Autodesk Fusion 360 part; units mm, degrees
(part 2 of 2)
ref_plane "WorkPlane31" through (0, 0, 67) normal (0, 0, 1) x (1, 0, 0) in component "02 LID - LCD buttons LEDs"
sketch "V2 text STATUS INDICATORS" plane through (0, 0, 67) normal (0, 0, 1) x (1, 0, 0) in component "02 LID - LCD buttons LEDs"
  line L0 (30, 13) -> (110, 13) construction
  line L1 (110, 13) -> (110, 19) construction
  line L2 (110, 19) -> (30, 19) construction
  line L3 (30, 19) -> (30, 13) construction
  dimension "d425" = 2.5
  text T0 "STATUS INDICATORS" font "Arial" height 2.5 align centre middle in box 80 x 6 at (30, 13) x (1, 0) y (0, 1) spacing 1 kerned
extrude "V2 engrave STATUS INDICATORS" cut sketch "V2 text STATUS INDICATORS" against normal blind 0.35 text T0 bodies 2 in component "02 LID - LCD buttons LEDs"
ref_plane "WorkPlane1" through (0, 0, 67) normal (0, 0, 1) x (1, 0, 0) in component "V2 removable control fascia"
sketch "Control fascia plate sketch" plane through (0, 0, 67) normal (0, 0, 1) x (1, 0, 0) in component "V2 removable control fascia"
  line L0 (42, 22) -> (98, 22)
  line L1 (102, 26) -> (102, 68)
  line L2 (98, 72) -> (42, 72)
  line L3 (38, 68) -> (38, 26)
  arc A0 (98, 22) -> (102, 26) centre (98, 26) ccw
  arc A1 (102, 68) -> (98, 72) centre (98, 68) ccw
  arc A2 (42, 72) -> (38, 68) centre (42, 68) ccw
  arc A3 (38, 26) -> (42, 22) centre (42, 26) ccw
extrude "Control fascia plate" add sketch "Control fascia plate sketch" along normal blind 2.5 separate body makes body 11 in component "V2 removable control fascia"
ref_plane "WorkPlane2" through (0, 0, 66.9) normal (0, 0, 1) x (1, 0, 0) in component "V2 removable control fascia"
sketch "Fascia M3 clearance sketch" plane through (0, 0, 66.9) normal (0, 0, 1) x (1, 0, 0) in component "V2 removable control fascia"
  circle A0 centre (43, 32) radius 1.7
  circle A1 centre (97, 32) radius 1.7
  circle A2 centre (43, 62) radius 1.7
  circle A3 centre (97, 62) radius 1.7
extrude "Fascia M3 clearance" cut sketch "Fascia M3 clearance sketch" along normal blind 2.8 bodies 11 in component "V2 removable control fascia"
ref_plane "WorkPlane3" through (0, 0, 66.9) normal (0, 0, 1) x (1, 0, 0) in component "V2 removable control fascia"
sketch "Tactile actuator guide holes sketch" plane through (0, 0, 66.9) normal (0, 0, 1) x (1, 0, 0) in component "V2 removable control fascia"
  circle A0 centre (62.38, 53) radius 3.05
  circle A1 centre (70, 53) radius 3.05
  circle A2 centre (77.62, 53) radius 3.05
extrude "Tactile actuator guide holes" cut sketch "Tactile actuator guide holes sketch" along normal blind 2.8 bodies 11 in component "V2 removable control fascia"
ref_plane "WorkPlane4" through (0, 0, 66.9) normal (0, 0, 1) x (1, 0, 0) in component "V2 removable control fascia"
sketch "LED common viewing window sketch" plane through (0, 0, 66.9) normal (0, 0, 1) x (1, 0, 0) in component "V2 removable control fascia"
  line L0 (61, 35) -> (79, 35)
  line L1 (81, 37) -> (81, 41)
  line L2 (79, 43) -> (61, 43)
  line L3 (59, 41) -> (59, 37)
  arc A0 (79, 35) -> (81, 37) centre (79, 37) ccw
  arc A1 (81, 41) -> (79, 43) centre (79, 41) ccw
  arc A2 (61, 43) -> (59, 41) centre (61, 41) ccw
  arc A3 (59, 37) -> (61, 35) centre (61, 37) ccw
extrude "LED common viewing window" cut sketch "LED common viewing window sketch" along normal blind 2.8 bodies 11 in component "V2 removable control fascia"
ref_plane "WorkPlane5" through (0, 0, 69.5) normal (0, 0, 1) x (1, 0, 0) in component "V2 removable control fascia"
sketch "V2 text 1" plane through (0, 0, 69.5) normal (0, 0, 1) x (1, 0, 0) in component "V2 removable control fascia"
  line L0 (58.88, 59) -> (65.88, 59) construction
  line L1 (65.88, 59) -> (65.88, 65) construction
  line L2 (65.88, 65) -> (58.88, 65) construction
  line L3 (58.88, 65) -> (58.88, 59) construction
  dimension "d447" = 2.5
  dimension "d448" = 0
  text T0 "1" font "Arial" height 2.5 align centre middle in box 7 x 6 at (58.88, 59) x (1, 0) y (0, 1) spacing 1 kerned
extrude "V2 engrave 1" cut sketch "V2 text 1" against normal blind 0.35 text T0 bodies 11 in component "V2 removable control fascia"
ref_plane "WorkPlane6" through (0, 0, 69.5) normal (0, 0, 1) x (1, 0, 0) in component "V2 removable control fascia"
sketch "V2 text 2" plane through (0, 0, 69.5) normal (0, 0, 1) x (1, 0, 0) in component "V2 removable control fascia"
  line L0 (66.5, 59) -> (73.5, 59) construction
  line L1 (73.5, 59) -> (73.5, 65) construction
  line L2 (73.5, 65) -> (66.5, 65) construction
  line L3 (66.5, 65) -> (66.5, 59) construction
  dimension "d453" = 2.5
  dimension "d454" = 0
  text T0 "2" font "Arial" height 2.5 align centre middle in box 7 x 6 at (66.5, 59) x (1, 0) y (0, 1) spacing 1 kerned
extrude "V2 engrave 2" cut sketch "V2 text 2" against normal blind 0.35 text T0 bodies 11 in component "V2 removable control fascia"
ref_plane "WorkPlane7" through (0, 0, 69.5) normal (0, 0, 1) x (1, 0, 0) in component "V2 removable control fascia"
sketch "V2 text 3" plane through (0, 0, 69.5) normal (0, 0, 1) x (1, 0, 0) in component "V2 removable control fascia"
  line L0 (74.12, 59) -> (81.12, 59) construction
  line L1 (81.12, 59) -> (81.12, 65) construction
  line L2 (81.12, 65) -> (74.12, 65) construction
  line L3 (74.12, 65) -> (74.12, 59) construction
  dimension "d459" = 2.5
  dimension "d460" = 0
  text T0 "3" font "Arial" height 2.5 align centre middle in box 7 x 6 at (74.12, 59) x (1, 0) y (0, 1) spacing 1 kerned
extrude "V2 engrave 3" cut sketch "V2 text 3" against normal blind 0.35 text T0 bodies 11 in component "V2 removable control fascia"
ref_plane "WorkPlane32" through (0, 0, 63.9) normal (0, 0, 1) x (1, 0, 0) in component "02 LID - LCD buttons LEDs"
sketch "V2 carrier pillar clearance in lid sketch" plane through (0, 0, 63.9) normal (0, 0, 1) x (1, 0, 0) in component "02 LID - LCD buttons LEDs"
  circle A0 centre (45, 44) radius 4.1
  circle A1 centre (95, 44) radius 4.1
extrude "V2 carrier pillar clearance in lid" cut sketch "V2 carrier pillar clearance in lid sketch" along normal blind 3.3 bodies 2 in component "02 LID - LCD buttons LEDs"
ref_plane "WorkPlane8" through (0, 0, 49) normal (0, 0, 1) x (1, 0, 0) in component "V2 removable control fascia"
sketch "Control carrier standoffs sketch" plane through (0, 0, 49) normal (0, 0, 1) x (1, 0, 0) in component "V2 removable control fascia"
  circle A0 centre (45, 44) radius 3.5
  circle A1 centre (95, 44) radius 3.5
extrude "Control carrier standoffs" add sketch "Control carrier standoffs sketch" along normal blind 18 bodies 11 in component "V2 removable control fascia"
ref_plane "WorkPlane9" through (0, 0, 48.9) normal (0, 0, 1) x (1, 0, 0) in component "V2 removable control fascia"
sketch "Carrier M3 pilots sketch" plane through (0, 0, 48.9) normal (0, 0, 1) x (1, 0, 0) in component "V2 removable control fascia"
  circle A0 centre (45, 44) radius 1.25
  circle A1 centre (95, 44) radius 1.25
extrude "Carrier M3 pilots" cut sketch "Carrier M3 pilots sketch" along normal blind 8.1 bodies 11 in component "V2 removable control fascia"
ref_plane "WorkPlane1" through (0, 0, 46.5) normal (0, 0, 1) x (1, 0, 0) in component "V2 control PCB removable carrier"
sketch "Control PCB carrier sketch" plane through (0, 0, 46.5) normal (0, 0, 1) x (1, 0, 0) in component "V2 control PCB removable carrier"
  line L0 (42, 28) -> (98, 28)
  line L1 (100, 30) -> (100, 61)
  line L2 (98, 63) -> (42, 63)
  line L3 (40, 61) -> (40, 30)
  arc A0 (98, 28) -> (100, 30) centre (98, 30) ccw
  arc A1 (100, 61) -> (98, 63) centre (98, 61) ccw
  arc A2 (42, 63) -> (40, 61) centre (42, 61) ccw
  arc A3 (40, 30) -> (42, 28) centre (42, 30) ccw
extrude "Control PCB carrier" add sketch "Control PCB carrier sketch" along normal blind 2.5 separate body makes body 12 in component "V2 control PCB removable carrier"
ref_plane "WorkPlane2" through (0, 0, 46.4) normal (0, 0, 1) x (1, 0, 0) in component "V2 control PCB removable carrier"
sketch "Carrier M3 through sketch" plane through (0, 0, 46.4) normal (0, 0, 1) x (1, 0, 0) in component "V2 control PCB removable carrier"
  circle A0 centre (45, 44) radius 1.7
  circle A1 centre (95, 44) radius 1.7
extrude "Carrier M3 through" cut sketch "Carrier M3 through sketch" along normal blind 2.8 bodies 12 in component "V2 control PCB removable carrier"
ref_plane "WorkPlane3" through (0, 0, 49) normal (0, 0, 1) x (1, 0, 0) in component "V2 control PCB removable carrier"
sketch "Control PCB corner support pads" plane through (0, 0, 49) normal (0, 0, 1) x (1, 0, 0) in component "V2 control PCB removable carrier"
  line L0 (54, 30) -> (57, 30)
  line L1 (57, 30) -> (57, 33)
  line L2 (57, 33) -> (54, 33)
  line L3 (54, 33) -> (54, 30)
  line L4 (54, 57) -> (57, 57)
  line L5 (57, 57) -> (57, 60)
  line L6 (57, 60) -> (54, 60)
  line L7 (54, 60) -> (54, 57)
  line L8 (83, 30) -> (86, 30)
  line L9 (86, 30) -> (86, 33)
  line L10 (86, 33) -> (83, 33)
  line L11 (83, 33) -> (83, 30)
  line L12 (83, 57) -> (86, 57)
  line L13 (86, 57) -> (86, 60)
  line L14 (86, 60) -> (83, 60)
  line L15 (83, 60) -> (83, 57)
extrude "PCB stand-off pads" add sketch "Control PCB corner support pads" along normal blind 4 bodies 12 in component "V2 control PCB removable carrier"
ref_plane "WorkPlane4" through (0, 0, 49) normal (0, 0, 1) x (1, 0, 0) in component "V2 control PCB removable carrier"
sketch "Control PCB guide sketch" plane through (0, 0, 49) normal (0, 0, 1) x (1, 0, 0) in component "V2 control PCB removable carrier"
  line L0 (51.5, 30) -> (53.5, 30)
  line L1 (53.5, 30) -> (53.5, 60)
  line L2 (53.5, 60) -> (51.5, 60)
  line L3 (51.5, 60) -> (51.5, 30)
extrude "Control PCB guide" add sketch "Control PCB guide sketch" along normal blind 5 bodies 12 in component "V2 control PCB removable carrier"
ref_plane "WorkPlane5" through (0, 0, 49) normal (0, 0, 1) x (1, 0, 0) in component "V2 control PCB removable carrier"
sketch "Control PCB guide sketch (1)" plane through (0, 0, 49) normal (0, 0, 1) x (1, 0, 0) in component "V2 control PCB removable carrier"
  line L0 (86.5, 30) -> (88.5, 30)
  line L1 (88.5, 30) -> (88.5, 60)
  line L2 (88.5, 60) -> (86.5, 60)
  line L3 (86.5, 60) -> (86.5, 30)
extrude "Control PCB guide (1)" add sketch "Control PCB guide sketch (1)" along normal blind 5 bodies 12 in component "V2 control PCB removable carrier"
ref_plane "WorkPlane6" through (0, 0, 49) normal (0, 0, 1) x (1, 0, 0) in component "V2 control PCB removable carrier"
sketch "Control PCB guide sketch (2)" plane through (0, 0, 49) normal (0, 0, 1) x (1, 0, 0) in component "V2 control PCB removable carrier"
  line L0 (54, 27.5) -> (86, 27.5)
  line L1 (86, 27.5) -> (86, 29.5)
  line L2 (86, 29.5) -> (54, 29.5)
  line L3 (54, 29.5) -> (54, 27.5)
extrude "Control PCB guide (2)" add sketch "Control PCB guide sketch (2)" along normal blind 5 bodies 12 in component "V2 control PCB removable carrier"
ref_plane "WorkPlane7" through (0, 0, 46.4) normal (0, 0, 1) x (1, 0, 0) in component "V2 control PCB removable carrier"
sketch "PCB retaining strap slot sketch" plane through (0, 0, 46.4) normal (0, 0, 1) x (1, 0, 0) in component "V2 control PCB removable carrier"
  line L0 (52, 48) -> (54, 48)
  line L1 (54, 48) -> (54, 54)
  line L2 (54, 54) -> (52, 54)
  line L3 (52, 54) -> (52, 48)
extrude "PCB retaining strap slot" cut sketch "PCB retaining strap slot sketch" along normal blind 2.8 bodies 12 in component "V2 control PCB removable carrier"
ref_plane "WorkPlane8" through (0, 0, 46.4) normal (0, 0, 1) x (1, 0, 0) in component "V2 control PCB removable carrier"
sketch "PCB retaining strap slot sketch (1)" plane through (0, 0, 46.4) normal (0, 0, 1) x (1, 0, 0) in component "V2 control PCB removable carrier"
  line L0 (85, 48) -> (87, 48)
  line L1 (87, 48) -> (87, 54)
  line L2 (87, 54) -> (85, 54)
  line L3 (85, 54) -> (85, 48)
extrude "PCB retaining strap slot (1)" cut sketch "PCB retaining strap slot sketch (1)" along normal blind 2.8 bodies 12 in component "V2 control PCB removable carrier"
ref_plane "WorkPlane1" through (0, 0, 58.6) normal (0, 0, 1) x (1, 0, 0) in component "V2 captured tactile plunger 1"
sketch "Tactile contact stem" plane through (0, 0, 58.6) normal (0, 0, 1) x (1, 0, 0) in component "V2 captured tactile plunger 1"
  circle A0 centre (62.38, 53) radius 2
extrude "Tactile contact stem (1)" add sketch "Tactile contact stem" along normal blind 8.2 separate body makes body 13 in component "V2 captured tactile plunger 1"
ref_plane "WorkPlane2" through (0, 0, 65.2) normal (0, 0, 1) x (1, 0, 0) in component "V2 captured tactile plunger 1"
sketch "Captive flange" plane through (0, 0, 65.2) normal (0, 0, 1) x (1, 0, 0) in component "V2 captured tactile plunger 1"
  circle A0 centre (62.38, 53) radius 3.5
extrude "Captive flange (1)" add sketch "Captive flange" along normal blind 1.6 bodies 13 in component "V2 captured tactile plunger 1"
ref_plane "WorkPlane3" through (0, 0, 66.8) normal (0, 0, 1) x (1, 0, 0) in component "V2 captured tactile plunger 1"
sketch "Finger tip" plane through (0, 0, 66.8) normal (0, 0, 1) x (1, 0, 0) in component "V2 captured tactile plunger 1"
  circle A0 centre (62.38, 53) radius 2.75
extrude "Finger tip (1)" add sketch "Finger tip" along normal blind 3.6 bodies 13 in component "V2 captured tactile plunger 1"
ref_plane "WorkPlane1" through (0, 0, 58.6) normal (0, 0, 1) x (1, 0, 0) in component "V2 captured tactile plunger 2"
sketch "Tactile contact stem (2)" plane through (0, 0, 58.6) normal (0, 0, 1) x (1, 0, 0) in component "V2 captured tactile plunger 2"
  circle A0 centre (70, 53) radius 2
extrude "Tactile contact stem (1)'" add sketch "Tactile contact stem (2)" along normal blind 8.2 separate body makes body 14 in component "V2 captured tactile plunger 2"
ref_plane "WorkPlane2" through (0, 0, 65.2) normal (0, 0, 1) x (1, 0, 0) in component "V2 captured tactile plunger 2"
sketch "Captive flange (2)" plane through (0, 0, 65.2) normal (0, 0, 1) x (1, 0, 0) in component "V2 captured tactile plunger 2"
  circle A0 centre (70, 53) radius 3.5
extrude "Captive flange (1)'" add sketch "Captive flange (2)" along normal blind 1.6 bodies 14 in component "V2 captured tactile plunger 2"
ref_plane "WorkPlane3" through (0, 0, 66.8) normal (0, 0, 1) x (1, 0, 0) in component "V2 captured tactile plunger 2"
sketch "Finger tip (2)" plane through (0, 0, 66.8) normal (0, 0, 1) x (1, 0, 0) in component "V2 captured tactile plunger 2"
  circle A0 centre (70, 53) radius 2.75
extrude "Finger tip (1)'" add sketch "Finger tip (2)" along normal blind 3.6 bodies 14 in component "V2 captured tactile plunger 2"
ref_plane "WorkPlane1" through (0, 0, 58.6) normal (0, 0, 1) x (1, 0, 0) in component "V2 captured tactile plunger 3"
sketch "Tactile contact stem (3)" plane through (0, 0, 58.6) normal (0, 0, 1) x (1, 0, 0) in component "V2 captured tactile plunger 3"
  circle A0 centre (77.62, 53) radius 2
extrude "Tactile contact stem (1)''" add sketch "Tactile contact stem (3)" along normal blind 8.2 separate body makes body 15 in component "V2 captured tactile plunger 3"
ref_plane "WorkPlane2" through (0, 0, 65.2) normal (0, 0, 1) x (1, 0, 0) in component "V2 captured tactile plunger 3"
sketch "Captive flange (3)" plane through (0, 0, 65.2) normal (0, 0, 1) x (1, 0, 0) in component "V2 captured tactile plunger 3"
  circle A0 centre (77.62, 53) radius 3.5
extrude "Captive flange (1)''" add sketch "Captive flange (3)" along normal blind 1.6 bodies 15 in component "V2 captured tactile plunger 3"
ref_plane "WorkPlane3" through (0, 0, 66.8) normal (0, 0, 1) x (1, 0, 0) in component "V2 captured tactile plunger 3"
sketch "Finger tip (3)" plane through (0, 0, 66.8) normal (0, 0, 1) x (1, 0, 0) in component "V2 captured tactile plunger 3"
  circle A0 centre (77.62, 53) radius 2.75
extrude "Finger tip (1)''" add sketch "Finger tip (3)" along normal blind 3.6 bodies 15 in component "V2 captured tactile plunger 3"
ref_plane "WorkPlane1" through (0, 0, 8) normal (0, 0, 1) x (1, 0, 0) in component "REF main board 90x80x20 - photo estimate"
sketch "Main PCB sketch" plane through (0, 0, 8) normal (0, 0, 1) x (1, 0, 0) in component "REF main board 90x80x20 - photo estimate"
  line L0 (25, 20) -> (115, 20)
  line L1 (115, 20) -> (115, 100)
  line L2 (115, 100) -> (25, 100)
  line L3 (25, 100) -> (25, 20)
extrude "Main PCB" add sketch "Main PCB sketch" along normal blind 1.6 separate body makes body 16 in component "REF main board 90x80x20 - photo estimate"
ref_plane "WorkPlane2" through (0, 0, 9.6) normal (0, 0, 1) x (1, 0, 0) in component "REF main board 90x80x20 - photo estimate"
sketch "ESP32 reference sketch" plane through (0, 0, 9.6) normal (0, 0, 1) x (1, 0, 0) in component "REF main board 90x80x20 - photo estimate"
  line L0 (68, 38) -> (95, 38)
  line L1 (95, 38) -> (95, 88)
  line L2 (95, 88) -> (68, 88)
  line L3 (68, 88) -> (68, 38)
extrude "ESP32 reference" add sketch "ESP32 reference sketch" along normal blind 12 separate body makes body 17 in component "REF main board 90x80x20 - photo estimate"
ref_plane "WorkPlane3" through (0, 0, 9.6) normal (0, 0, 1) x (1, 0, 0) in component "REF main board 90x80x20 - photo estimate"
sketch "nRF24 reference sketch" plane through (0, 0, 9.6) normal (0, 0, 1) x (1, 0, 0) in component "REF main board 90x80x20 - photo estimate"
  line L0 (33, 75) -> (68, 75)
  line L1 (68, 75) -> (68, 93)
  line L2 (68, 93) -> (33, 93)
  line L3 (33, 93) -> (33, 75)
extrude "nRF24 reference" add sketch "nRF24 reference sketch" along normal blind 10 separate body makes body 18 in component "REF main board 90x80x20 - photo estimate"
ref_plane "WorkPlane4" through (0, 0, 9.6) normal (0, 0, 1) x (1, 0, 0) in component "REF main board 90x80x20 - photo estimate"
sketch "MPU6050 reference sketch" plane through (0, 0, 9.6) normal (0, 0, 1) x (1, 0, 0) in component "REF main board 90x80x20 - photo estimate"
  line L0 (36, 34) -> (57, 34)
  line L1 (57, 34) -> (57, 50)
  line L2 (57, 50) -> (36, 50)
  line L3 (36, 50) -> (36, 34)
extrude "MPU6050 reference" add sketch "MPU6050 reference sketch" along normal blind 6 separate body makes body 19 in component "REF main board 90x80x20 - photo estimate"
ref_plane "WorkPlane5" through (0, 0, 9.6) normal (0, 0, 1) x (1, 0, 0) in component "REF main board 90x80x20 - photo estimate"
sketch "Tallest component 20mm total sketch" plane through (0, 0, 9.6) normal (0, 0, 1) x (1, 0, 0) in component "REF main board 90x80x20 - photo estimate"
  line L0 (62, 22) -> (72, 22)
  line L1 (72, 22) -> (72, 32)
  line L2 (72, 32) -> (62, 32)
  line L3 (62, 32) -> (62, 22)
extrude "Tallest component 20mm total" add sketch "Tallest component 20mm total sketch" along normal blind 18.4 separate body makes body 20 in component "REF main board 90x80x20 - photo estimate"
ref_plane "WorkPlane6" through (0, 0, 11) normal (0, 0, 1) x (1, 0, 0) in component "REF main board 90x80x20 - photo estimate"
sketch "Rocker switch side clearance sketch" plane through (0, 0, 11) normal (0, 0, 1) x (1, 0, 0) in component "REF main board 90x80x20 - photo estimate"
  line L0 (18, 23) -> (25, 23)
  line L1 (25, 23) -> (25, 39)
  line L2 (25, 39) -> (18, 39)
  line L3 (18, 39) -> (18, 23)
extrude "Rocker switch side clearance" add sketch "Rocker switch side clearance sketch" along normal blind 12 separate body makes body 21 in component "REF main board 90x80x20 - photo estimate"
ref_plane "WorkPlane7" through (0, 0, 13) normal (0, 0, 1) x (1, 0, 0) in component "REF main board 90x80x20 - photo estimate"
sketch "SMA connector space sketch" plane through (0, 0, 13) normal (0, 0, 1) x (1, 0, 0) in component "REF main board 90x80x20 - photo estimate"
  line L0 (16, 80) -> (25, 80)
  line L1 (25, 80) -> (25, 86)
  line L2 (25, 86) -> (16, 86)
  line L3 (16, 86) -> (16, 80)
extrude "SMA connector space" add sketch "SMA connector space sketch" along normal blind 6 separate body makes body 22 in component "REF main board 90x80x20 - photo estimate"
ref_plane "WorkPlane1" through (0, 0, 8) normal (0, 0, 1) x (1, 0, 0) in component "REF four relay board 70x50x20"
sketch "Relay PCB sketch" plane through (0, 0, 8) normal (0, 0, 1) x (1, 0, 0) in component "REF four relay board 70x50x20"
  line L0 (35, 117) -> (105, 117)
  line L1 (105, 117) -> (105, 167)
  line L2 (105, 167) -> (35, 167)
  line L3 (35, 167) -> (35, 117)
extrude "Relay PCB" add sketch "Relay PCB sketch" along normal blind 1.6 separate body makes body 23 in component "REF four relay board 70x50x20"
ref_plane "WorkPlane2" through (0, 0, 9.6) normal (0, 0, 1) x (1, 0, 0) in component "REF four relay board 70x50x20"
sketch "Relay 1 sketch" plane through (0, 0, 9.6) normal (0, 0, 1) x (1, 0, 0) in component "REF four relay board 70x50x20"
  line L0 (38, 133) -> (53, 133)
  line L1 (53, 133) -> (53, 152)
  line L2 (53, 152) -> (38, 152)
  line L3 (38, 152) -> (38, 133)
extrude "Relay 1" add sketch "Relay 1 sketch" along normal blind 15.5 separate body makes body 24 in component "REF four relay board 70x50x20"
ref_plane "WorkPlane3" through (0, 0, 9.6) normal (0, 0, 1) x (1, 0, 0) in component "REF four relay board 70x50x20"
sketch "Relay 2 sketch" plane through (0, 0, 9.6) normal (0, 0, 1) x (1, 0, 0) in component "REF four relay board 70x50x20"
  line L0 (54, 133) -> (69, 133)
  line L1 (69, 133) -> (69, 152)
  line L2 (69, 152) -> (54, 152)
  line L3 (54, 152) -> (54, 133)
extrude "Relay 2" add sketch "Relay 2 sketch" along normal blind 15.5 separate body makes body 25 in component "REF four relay board 70x50x20"
ref_plane "WorkPlane4" through (0, 0, 9.6) normal (0, 0, 1) x (1, 0, 0) in component "REF four relay board 70x50x20"
sketch "Relay 3 sketch" plane through (0, 0, 9.6) normal (0, 0, 1) x (1, 0, 0) in component "REF four relay board 70x50x20"
  line L0 (70, 133) -> (85, 133)
  line L1 (85, 133) -> (85, 152)
  line L2 (85, 152) -> (70, 152)
  line L3 (70, 152) -> (70, 133)
extrude "Relay 3" add sketch "Relay 3 sketch" along normal blind 15.5 separate body makes body 26 in component "REF four relay board 70x50x20"
ref_plane "WorkPlane5" through (0, 0, 9.6) normal (0, 0, 1) x (1, 0, 0) in component "REF four relay board 70x50x20"
sketch "Relay 4 sketch" plane through (0, 0, 9.6) normal (0, 0, 1) x (1, 0, 0) in component "REF four relay board 70x50x20"
  line L0 (86, 133) -> (101, 133)
  line L1 (101, 133) -> (101, 152)
  line L2 (101, 152) -> (86, 152)
  line L3 (86, 152) -> (86, 133)
extrude "Relay 4" add sketch "Relay 4 sketch" along normal blind 15.5 separate body makes body 27 in component "REF four relay board 70x50x20"
ref_plane "WorkPlane6" through (0, 0, 9.6) normal (0, 0, 1) x (1, 0, 0) in component "REF four relay board 70x50x20"
sketch "Screw terminal strip sketch" plane through (0, 0, 9.6) normal (0, 0, 1) x (1, 0, 0) in component "REF four relay board 70x50x20"
  line L0 (38, 155) -> (100, 155)
  line L1 (100, 155) -> (100, 165)
  line L2 (100, 165) -> (38, 165)
  line L3 (38, 165) -> (38, 155)
extrude "Screw terminal strip" add sketch "Screw terminal strip sketch" along normal blind 12 separate body makes body 28 in component "REF four relay board 70x50x20"
ref_plane "WorkPlane7" through (0, 0, 9.6) normal (0, 0, 1) x (1, 0, 0) in component "REF four relay board 70x50x20"
sketch "Relay control connector envelope sketch" plane through (0, 0, 9.6) normal (0, 0, 1) x (1, 0, 0) in component "REF four relay board 70x50x20"
  line L0 (42, 119) -> (77, 119)
  line L1 (77, 119) -> (77, 124)
  line L2 (77, 124) -> (42, 124)
  line L3 (42, 124) -> (42, 119)
extrude "Relay control connector envelope" add sketch "Relay control connector envelope sketch" along normal blind 18.4 separate body makes body 29 in component "REF four relay board 70x50x20"
ref_plane "WorkPlane1" through (0, 0, 52.4) normal (0, 0, 1) x (1, 0, 0) in component "REF LCD2004 98x60 - estimated from photo"
sketch "LCD PCB sketch" plane through (0, 0, 52.4) normal (0, 0, 1) x (1, 0, 0) in component "REF LCD2004 98x60 - estimated from photo"
  line L0 (21, 98) -> (119, 98)
  line L1 (119, 98) -> (119, 158)
  line L2 (119, 158) -> (21, 158)
  line L3 (21, 158) -> (21, 98)
extrude "LCD PCB" add sketch "LCD PCB sketch" along normal blind 1.6 separate body makes body 30 in component "REF LCD2004 98x60 - estimated from photo"
ref_plane "WorkPlane2" through (0, 0, 52.3) normal (0, 0, 1) x (1, 0, 0) in component "REF LCD2004 98x60 - estimated from photo"
sketch "LCD reference mounting holes sketch" plane through (0, 0, 52.3) normal (0, 0, 1) x (1, 0, 0) in component "REF LCD2004 98x60 - estimated from photo"
  circle A0 centre (23.5, 100.5) radius 1.6
  circle A1 centre (116.5, 100.5) radius 1.6
  circle A2 centre (23.5, 155.5) radius 1.6
  circle A3 centre (116.5, 155.5) radius 1.6
extrude "LCD reference mounting holes" cut sketch "LCD reference mounting holes sketch" along normal blind 1.8 bodies 30 in component "REF LCD2004 98x60 - estimated from photo"
ref_plane "WorkPlane3" through (0, 0, 54) normal (0, 0, 1) x (1, 0, 0) in component "REF LCD2004 98x60 - estimated from photo"
sketch "LCD bezel sketch" plane through (0, 0, 54) normal (0, 0, 1) x (1, 0, 0) in component "REF LCD2004 98x60 - estimated from photo"
  line L0 (21.5, 108.5) -> (118.5, 108.5)
  line L1 (118.5, 108.5) -> (118.5, 147.5)
  line L2 (118.5, 147.5) -> (21.5, 147.5)
  line L3 (21.5, 147.5) -> (21.5, 108.5)
extrude "LCD bezel" add sketch "LCD bezel sketch" along normal blind 9.5 separate body makes body 31 in component "REF LCD2004 98x60 - estimated from photo"
ref_plane "WorkPlane4" through (0, 0, 63.5) normal (0, 0, 1) x (1, 0, 0) in component "REF LCD2004 98x60 - estimated from photo"
sketch "LCD glass sketch" plane through (0, 0, 63.5) normal (0, 0, 1) x (1, 0, 0) in component "REF LCD2004 98x60 - estimated from photo"
  line L0 (32, 115.4) -> (108, 115.4)
  line L1 (108, 115.4) -> (108, 140.6)
  line L2 (108, 140.6) -> (32, 140.6)
  line L3 (32, 140.6) -> (32, 115.4)
extrude "LCD glass" add sketch "LCD glass sketch" along normal blind 0.3 separate body makes body 32 in component "REF LCD2004 98x60 - estimated from photo"
ref_plane "WorkPlane5" through (0, 0, 42) normal (0, 0, 1) x (1, 0, 0) in component "REF LCD2004 98x60 - estimated from photo"
sketch "LCD backpack reserve sketch" plane through (0, 0, 42) normal (0, 0, 1) x (1, 0, 0) in component "REF LCD2004 98x60 - estimated from photo"
  line L0 (32, 100) -> (74, 100)
  line L1 (74, 100) -> (74, 118)
  line L2 (74, 118) -> (32, 118)
  line L3 (32, 118) -> (32, 100)
extrude "LCD backpack reserve" add sketch "LCD backpack reserve sketch" along normal blind 10.4 separate body makes body 33 in component "REF LCD2004 98x60 - estimated from photo"
ref_plane "WorkPlane1" through (0, 0, 53) normal (0, 0, 1) x (1, 0, 0) in component "REF actual combined buttons LEDs PCB - estimated"
sketch "Control PCB estimated 30x30 sketch" plane through (0, 0, 53) normal (0, 0, 1) x (1, 0, 0) in component "REF actual combined buttons LEDs PCB - estimated"
  line L0 (55, 30) -> (85, 30)
  line L1 (85, 30) -> (85, 60)
  line L2 (85, 60) -> (55, 60)
  line L3 (55, 60) -> (55, 30)
extrude "Control PCB estimated 30x30" add sketch "Control PCB estimated 30x30 sketch" along normal blind 1.6 separate body makes body 34 in component "REF actual combined buttons LEDs PCB - estimated"
ref_plane "WorkPlane2" through (0, 0, 54.6) normal (0, 0, 1) x (1, 0, 0) in component "REF actual combined buttons LEDs PCB - estimated"
sketch "Tactile switch 6x6 sketch" plane through (0, 0, 54.6) normal (0, 0, 1) x (1, 0, 0) in component "REF actual combined buttons LEDs PCB - estimated"
  line L0 (59.38, 50) -> (65.38, 50)
  line L1 (65.38, 50) -> (65.38, 56)
  line L2 (65.38, 56) -> (59.38, 56)
  line L3 (59.38, 56) -> (59.38, 50)
extrude "Tactile switch 6x6" add sketch "Tactile switch 6x6 sketch" along normal blind 3.3 separate body makes body 35 in component "REF actual combined buttons LEDs PCB - estimated"
ref_plane "WorkPlane3" through (0, 0, 57.9) normal (0, 0, 1) x (1, 0, 0) in component "REF actual combined buttons LEDs PCB - estimated"
sketch "Switch actuator" plane through (0, 0, 57.9) normal (0, 0, 1) x (1, 0, 0) in component "REF actual combined buttons LEDs PCB - estimated"
  circle A0 centre (62.38, 53) radius 1.65
extrude "Switch actuator (1)" add sketch "Switch actuator" along normal blind 0.5 separate body makes body 36 in component "REF actual combined buttons LEDs PCB - estimated"
ref_plane "WorkPlane4" through (0, 0, 54.6) normal (0, 0, 1) x (1, 0, 0) in component "REF actual combined buttons LEDs PCB - estimated"
sketch "Tactile switch 6x6 sketch (1)" plane through (0, 0, 54.6) normal (0, 0, 1) x (1, 0, 0) in component "REF actual combined buttons LEDs PCB - estimated"
  line L0 (67, 50) -> (73, 50)
  line L1 (73, 50) -> (73, 56)
  line L2 (73, 56) -> (67, 56)
  line L3 (67, 56) -> (67, 50)
extrude "Tactile switch 6x6 (1)" add sketch "Tactile switch 6x6 sketch (1)" along normal blind 3.3 separate body makes body 37 in component "REF actual combined buttons LEDs PCB - estimated"
ref_plane "WorkPlane5" through (0, 0, 57.9) normal (0, 0, 1) x (1, 0, 0) in component "REF actual combined buttons LEDs PCB - estimated"
sketch "Switch actuator (1)" plane through (0, 0, 57.9) normal (0, 0, 1) x (1, 0, 0) in component "REF actual combined buttons LEDs PCB - estimated"
  circle A0 centre (70, 53) radius 1.65
extrude "Switch actuator (2)" add sketch "Switch actuator (1)" along normal blind 0.5 separate body makes body 38 in component "REF actual combined buttons LEDs PCB - estimated"
ref_plane "WorkPlane6" through (0, 0, 54.6) normal (0, 0, 1) x (1, 0, 0) in component "REF actual combined buttons LEDs PCB - estimated"
sketch "Tactile switch 6x6 sketch (2)" plane through (0, 0, 54.6) normal (0, 0, 1) x (1, 0, 0) in component "REF actual combined buttons LEDs PCB - estimated"
  line L0 (74.62, 50) -> (80.62, 50)
  line L1 (80.62, 50) -> (80.62, 56)
  line L2 (80.62, 56) -> (74.62, 56)
  line L3 (74.62, 56) -> (74.62, 50)
extrude "Tactile switch 6x6 (2)" add sketch "Tactile switch 6x6 sketch (2)" along normal blind 3.3 separate body makes body 39 in component "REF actual combined buttons LEDs PCB - estimated"
ref_plane "WorkPlane7" through (0, 0, 57.9) normal (0, 0, 1) x (1, 0, 0) in component "REF actual combined buttons LEDs PCB - estimated"
sketch "Switch actuator (2)" plane through (0, 0, 57.9) normal (0, 0, 1) x (1, 0, 0) in component "REF actual combined buttons LEDs PCB - estimated"
  circle A0 centre (77.62, 53) radius 1.65
extrude "Switch actuator (3)" add sketch "Switch actuator (2)" along normal blind 0.5 separate body makes body 40 in component "REF actual combined buttons LEDs PCB - estimated"
ref_plane "WorkPlane8" through (0, 0, 54.6) normal (0, 0, 1) x (1, 0, 0) in component "REF actual combined buttons LEDs PCB - estimated"
sketch "LED BLUE" plane through (0, 0, 54.6) normal (0, 0, 1) x (1, 0, 0) in component "REF actual combined buttons LEDs PCB - estimated"
  circle A0 centre (63.65, 39) radius 1.5
extrude "LED BLUE (1)" add sketch "LED BLUE" along normal blind 4.5 separate body makes body 41 in component "REF actual combined buttons LEDs PCB - estimated"
ref_plane "WorkPlane9" through (0, 0, 54.6) normal (0, 0, 1) x (1, 0, 0) in component "REF actual combined buttons LEDs PCB - estimated"
sketch "LED RED" plane through (0, 0, 54.6) normal (0, 0, 1) x (1, 0, 0) in component "REF actual combined buttons LEDs PCB - estimated"
  circle A0 centre (70, 39) radius 1.5
extrude "LED RED (1)" add sketch "LED RED" along normal blind 4.5 separate body makes body 42 in component "REF actual combined buttons LEDs PCB - estimated"
ref_plane "WorkPlane10" through (0, 0, 54.6) normal (0, 0, 1) x (1, 0, 0) in component "REF actual combined buttons LEDs PCB - estimated"
sketch "LED GREEN" plane through (0, 0, 54.6) normal (0, 0, 1) x (1, 0, 0) in component "REF actual combined buttons LEDs PCB - estimated"
  circle A0 centre (76.35, 39) radius 1.5
extrude "LED GREEN (1)" add sketch "LED GREEN" along normal blind 4.5 separate body makes body 43 in component "REF actual combined buttons LEDs PCB - estimated"
ref_plane "WorkPlane23" through (0, 0, 14) normal (0, 0, 1) x (1, 0, 0) in component "01 BASE - PCB at bottom"
sketch "V2 repaired rear cable outlet sketch" plane through (0, 0, 14) normal (0, 0, 1) x (1, 0, 0) in component "01 BASE - PCB at bottom"
  line L0 (38, 176.5) -> (62, 176.5)
  line L1 (62, 176.5) -> (62, 180.5)
  line L2 (62, 180.5) -> (38, 180.5)
  line L3 (38, 180.5) -> (38, 176.5)
extrude "V2 repaired rear cable outlet" cut sketch "V2 repaired rear cable outlet sketch" along normal blind 10 bodies 1 in component "01 BASE - PCB at bottom"
ref_plane "WorkPlane24" through (0, 0, 14) normal (0, 0, 1) x (1, 0, 0) in component "01 BASE - PCB at bottom"
sketch "V2 repaired rear cable outlet sketch (1)" plane through (0, 0, 14) normal (0, 0, 1) x (1, 0, 0) in component "01 BASE - PCB at bottom"
  line L0 (78, 176.5) -> (102, 176.5)
  line L1 (102, 176.5) -> (102, 180.5)
  line L2 (102, 180.5) -> (78, 180.5)
  line L3 (78, 180.5) -> (78, 176.5)
extrude "V2 repaired rear cable outlet (1)" cut sketch "V2 repaired rear cable outlet sketch (1)" along normal blind 10 bodies 1 in component "01 BASE - PCB at bottom"
ref_plane "WorkPlane25" through (0, 0, 3) normal (0, 0, 1) x (1, 0, 0) in component "01 BASE - PCB at bottom"
sketch "V2 relocated switch-side clamp pedestal sketch" plane through (0, 0, 3) normal (0, 0, 1) x (1, 0, 0) in component "01 BASE - PCB at bottom"
  circle A0 centre (20, 48) radius 4
extrude "V2 relocated switch-side clamp pedestal" add sketch "V2 relocated switch-side clamp pedestal sketch" along normal blind 6.6 bodies 1 in component "01 BASE - PCB at bottom"
ref_plane "WorkPlane26" through (0, 0, 3) normal (0, 0, 1) x (1, 0, 0) in component "01 BASE - PCB at bottom"
sketch "V2 relocated main PCB support sketch" plane through (0, 0, 3) normal (0, 0, 1) x (1, 0, 0) in component "01 BASE - PCB at bottom"
  line L0 (23, 43) -> (29, 43)
  line L1 (29, 43) -> (29, 53)
  line L2 (29, 53) -> (23, 53)
  line L3 (23, 53) -> (23, 43)
extrude "V2 relocated main PCB support" add sketch "V2 relocated main PCB support sketch" along normal blind 5 bodies 1 in component "01 BASE - PCB at bottom"
ref_plane "WorkPlane27" through (0, 0, 3.1) normal (0, 0, 1) x (1, 0, 0) in component "01 BASE - PCB at bottom"
sketch "V2 relocated clamp pilot sketch" plane through (0, 0, 3.1) normal (0, 0, 1) x (1, 0, 0) in component "01 BASE - PCB at bottom"
  circle A0 centre (20, 48) radius 1.25
extrude "V2 relocated clamp pilot" cut sketch "V2 relocated clamp pilot sketch" along normal blind 6.6 bodies 1 in component "01 BASE - PCB at bottom"
ref_plane "WorkPlane9" through (0, 0, 46.4) normal (0, 0, 1) x (1, 0, 0) in component "V2 control PCB removable carrier"
sketch "V2 front margin retaining strap slot sketch" plane through (0, 0, 46.4) normal (0, 0, 1) x (1, 0, 0) in component "V2 control PCB removable carrier"
  line L0 (52, 31) -> (54, 31)
  line L1 (54, 31) -> (54, 35)
  line L2 (54, 35) -> (52, 35)
  line L3 (52, 35) -> (52, 31)
extrude "V2 front margin retaining strap slot" cut sketch "V2 front margin retaining strap slot sketch" along normal blind 2.8 bodies 12 in component "V2 control PCB removable carrier"
ref_plane "WorkPlane10" through (0, 0, 46.4) normal (0, 0, 1) x (1, 0, 0) in component "V2 control PCB removable carrier"
sketch "V2 front margin retaining strap slot sketch (1)" plane through (0, 0, 46.4) normal (0, 0, 1) x (1, 0, 0) in component "V2 control PCB removable carrier"
  line L0 (85, 31) -> (87, 31)
  line L1 (87, 31) -> (87, 35)
  line L2 (87, 35) -> (85, 35)
  line L3 (85, 35) -> (85, 31)
extrude "V2 front margin retaining strap slot (1)" cut sketch "V2 front margin retaining strap slot sketch (1)" along normal blind 2.8 bodies 12 in component "V2 control PCB removable carrier"
move_body "V2 permanent clamp clearance correction" bodies 3 to x (1, 0, 0) y (0, 1, 0) z (0, 0, 1) at (0, 13, 0) in component "V2 MAIN clamp 1"
move_body "V2 permanent clamp clearance correction'" bodies 9 to x (1, 0, 0) y (0, 1, 0) z (0, 0, 1) at (-0.8, 0, 0) in component "V2 RELAY clamp 3"
component "01 BASE - PCB at bottom" placed x (1, 0, 0) y (0, 1, 0) z (0, 0, 1) at (0, 0, 0)
component "02 LID - LCD buttons LEDs" placed x (1, 0, 0) y (0, 1, 0) z (0, 0, 1) at (0, 0, 0)
component "V2 MAIN clamp 1" placed x (1, 0, 0) y (0, 1, 0) z (0, 0, 1) at (0, 0, 0)
component "V2 MAIN clamp 2" placed x (1, 0, 0) y (0, 1, 0) z (0, 0, 1) at (0, 0, 0)
component "V2 MAIN clamp 3" placed x (1, 0, 0) y (0, 1, 0) z (0, 0, 1) at (0, 0, 0)
component "V2 MAIN clamp 4" placed x (1, 0, 0) y (0, 1, 0) z (0, 0, 1) at (0, 0, 0)
component "V2 RELAY clamp 1" placed x (1, 0, 0) y (0, 1, 0) z (0, 0, 1) at (0, 0, 0)
component "V2 RELAY clamp 2" placed x (1, 0, 0) y (0, 1, 0) z (0, 0, 1) at (0, 0, 0)
component "V2 RELAY clamp 3" placed x (1, 0, 0) y (0, 1, 0) z (0, 0, 1) at (0, 0, 0)
component "V2 RELAY clamp 4" placed x (1, 0, 0) y (0, 1, 0) z (0, 0, 1) at (0, 0, 0)
component "V2 removable control fascia" placed x (1, 0, 0) y (0, 1, 0) z (0, 0, 1) at (0, 0, 0)
component "V2 control PCB removable carrier" placed x (1, 0, 0) y (0, 1, 0) z (0, 0, 1) at (0, 0, 0)
component "V2 captured tactile plunger 1" placed x (1, 0, 0) y (0, 1, 0) z (0, 0, 1) at (0, 0, 0)
component "V2 captured tactile plunger 2" placed x (1, 0, 0) y (0, 1, 0) z (0, 0, 1) at (0, 0, 0)
component "V2 captured tactile plunger 3" placed x (1, 0, 0) y (0, 1, 0) z (0, 0, 1) at (0, 0, 0)
component "REF main board 90x80x20 - photo estimate" placed x (1, 0, 0) y (0, 1, 0) z (0, 0, 1) at (0, 0, 0)
component "REF four relay board 70x50x20" placed x (1, 0, 0) y (0, 1, 0) z (0, 0, 1) at (0, 0, 0)
component "REF LCD2004 98x60 - estimated from photo" placed x (1, 0, 0) y (0, 1, 0) z (0, 0, 1) at (0, 0, 0)
component "REF actual combined buttons LEDs PCB - estimated" placed x (1, 0, 0) y (0, 1, 0) z (0, 0, 1) at (0, 0, 0)
component "01 BASE - PCB at bottom" placed x (1, 0, 0) y (0, 1, 0) z (0, 0, 1) at (0, 0, 0) in component "V2 RELAY clamp 2"
equation "button_d = 12.2 mm" comment "ASSUMED: measure actual panel button"
equation "led_d = 5.2 mm" comment "ASSUMED: 5 mm LED clearance"
equation "screw_clearance = 3.4 mm" comment "M3 clearance"
equation "pilot_d = 2.5 mm" comment "Plastic tapping pilot; verify printed fit"
equation "d17 = pilot_d"
equation "d18 = pilot_d"
equation "d19 = pilot_d"
equation "d20 = pilot_d"
equation "d37 = pilot_d"
equation "d38 = pilot_d"
equation "d39 = pilot_d"
equation "d40 = pilot_d"
equation "d53 = screw_clearance"
equation "d54 = screw_clearance"
equation "d55 = screw_clearance"
equation "d56 = screw_clearance"
equation "d73 = pilot_d"
equation "d74 = pilot_d"
equation "d75 = pilot_d"
equation "d76 = pilot_d"
equation "d81 = button_d"
equation "d82 = button_d"
equation "d83 = button_d"
equation "d88 = led_d"
equation "d89 = led_d"
equation "d90 = led_d"
equation "d96 = 'H2 PRO'"
equation "d102 = 'POWER'"
equation "d108 = 'LOCK'"
equation "d114 = 'PURGE'"
equation "d120 = 'POWER'"
equation "d126 = 'LOCK'"
equation "d132 = 'MODE'"
equation "d408 = 'H2 PRO'"
equation "d414 = 'BRAIN / CONTROL UNIT'"
equation "d420 = 'POWER   LOCK   PURGE'"
equation "d426 = 'STATUS INDICATORS'"
equation "d448 = '1'"
equation "d454 = '2'"
equation "d460 = '3'"
named bodies: "BASE_V2_PRINT", "LID_V2_PRINT", "Tactile contact stem", "Main PCB", "ESP32 reference", "nRF24 reference", "MPU6050 reference", "Tallest component 20mm total", "Rocker switch side clearance", "SMA connector space", "Relay PCB", "Relay 1", "Relay 2", "Relay 3", "Relay 4", "Screw terminal strip", "Relay control connector envelope", "LCD PCB", "LCD bezel", "LCD glass", "LCD backpack reserve", "Control PCB estimated 30x30", "Tactile switch 6x6", "Switch actuator", "Tactile switch 6x6 (1)", "Switch actuator (1)", "Tactile switch 6x6 (2)", "Switch actuator (2)", "LED BLUE", "LED RED", "LED GREEN"
